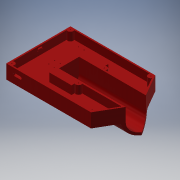
# Autodesk Inventor part: new base
Saved by Autodesk Inventor 2019 (Build 230136000, 136)
## iProperties
Created: 2019-03-15
Part Number: new base
Material: Generic
Document SubType Name: Modeling
Designer: Dell
Density: 1 g/cm^3
Appearance: Red
Mass: 2061.42 g
Surface Area: 3181.28 cm^2
Volume: 2061.42 cm^3
Author: Dell
Autodesk Inventor part; units mm, degrees
ref_plane "YZ Plane" through (0, 0, 0) normal (1, 0, 0) x (0, 1, 0)
ref_plane "XY Plane" through (0, 0, 0) normal (0, 0, 1) x (1, 0, 0)
sketch "Sketch2" plane through (0, 0, 0) normal (1, 0, 0) x (0, 1, 0)
  line L0 (50, 115) -> (0, 115)
  line L1 (0, 115) -> (0, 36)
  line L2 (0, 36) -> (50, 36)
  line L3 (50, 36) -> (50, 115)
  line L4 (50, -115) -> (0, -115)
  line L5 (0, -115) -> (0, -45)
  line L6 (0, -36) -> (50, -36)
  line L7 (50, -36) -> (50, -115)
  arc A0 (0, 45) -> (0, -45) centre (0, 0) ccw
  line L8 (0, 36) -> (0, -36)
  line L9 (0, 36) -> (0, -36)
  arc A1 (0, 36) -> (0, -36) centre (0, 0) ccw
  line L10 (0, -45) -> (0, -36)
  dimension "d7" = 50
  dimension "d8" = 79
  dimension "d12" = 90
  dimension "d14" = 50
  dimension "d16" = 72
  dimension "d117" = 79
  constraints: 23 end point, 5 point on circle, 5 point on line, 4 parallel, 3 collinear, 3 perpendicular, 2 centre point, 2 coincident, 2 horizontal, 1 midpoint, 1 vertical
  measures "d7" distance of L0.start L0.end
  measures "d8" distance of L2.end L0.start
  measures "d12" diameter of A0
  measures "d14" distance of L4.start L4.end
  measures "d16" diameter of A1
  measures "d117" distance of L4.end L6.start
extrude "Extrusion2" add sketch "Sketch2" along normal blind 370 contours L3 L2 L1 L0 | L1 A1 L10 A0 | L10 L6 L7 L4 L5
sketch "Sketch3" plane through (0, 50, -36) normal (0, 1, 0) x (1, 0, 0)
  line L0 (0, -72) -> (0, -151) projected
  line L1 (0, 0) -> (0, -72) projected
  line L2 (0, 79) -> (0, 0) projected
  line L3 (0, 79) -> (370, 79) projected
  line L4 (0, -151) -> (370, -151) projected
  line L5 (370, -72) -> (370, -151) projected
  line L6 (370, 0) -> (370, -72) projected
  line L7 (370, 79) -> (370, 0) projected
  line L8 (0, -151) -> (370, -151) projected
  line L9 (303.6047, -151) -> (370, -36)
  line L10 (370, -36) -> (303.6047, 79)
  line L11 (0, 79) -> (370, 79) projected
  line L12 (303.6047, -151) -> (370, -151)
  line L13 (370, -151) -> (370, 79)
  line L14 (370, 79) -> (303.6047, 79)
  line L15 (303.6047, -151) -> (303.6047, 79)
  point P0 (0, -36)
  dimension "d22" = 120
  dimension "d28" = 115
  constraints: 12 end point, 4 point on line, 1 horizontal, 1 midpoint, 1 parallel, 1 perpendicular, 1 vertical
  measures "d22" angle of L9 L10
  measures "d28" distance of L3.end L9.end
extrude "Extrusion3" cut sketch "Sketch3" against normal through all contours L9 L6 L5 L4 | L10 L3 L7 L6
sketch "Sketch4" plane through (0, 0, 0) normal (-1, 0, 0) x (0, 0, 1)
  arc A0 (-36, 0) -> (36, 0) centre (0, 0) ccw projected
  line L0 (36, 0) -> (36, 50) projected
  line L1 (-36, 50) -> (-36, 0) projected
  line L2 (36, 50) -> (-36, 50)
  constraints: 2 end point, 1 horizontal
extrude "Extrusion4" add sketch "Sketch4" against normal blind 110
sketch "Sketch5" plane through (0, 0, 0) normal (-1, 0, 0) x (0, 0, 1)
  arc A0 (-45, 0) -> (45, 0) centre (0, 0) ccw projected
  line L0 (45, 0) -> (-45, 0)
  constraints: 2 end point, 1 horizontal
extrude "Extrusion5" cut sketch "Sketch5" against normal blind 100
sketch "Sketch6" plane through (100, 0, 0) normal (-1, 0, 0) x (0, 0, 1)
  arc A0 (-45, 0) -> (45, 0) centre (0, 0) ccw projected
  arc A1 (-45, 0) -> (0, -45) centre (0, 0) ccw projected
  line L0 (45, 0) -> (115, 0) projected
  line L1 (-45, 0) -> (45, 0)
  constraints: 2 end point, 1 collinear
extrude "Extrusion6" add sketch "Sketch6" along normal blind 10
fillet "Fillet17" radius 10 1 edges at (90, 0, 0)
ref_plane "Work Plane1" through (0, -45, 0) normal (0, 1, 0) x (-1, 0, 0)
fillet "Fillet19" radius 10 4 edges at (85, 0, 45) (217.0096, 0, 45) (85, 0, -45) (217.0096, 0, -45)
sketch "Sketch26" plane through (0, -45, 0) normal (0, 1, 0) x (-1, 0, 0)
  circle A0 centre (-199.5, -1) radius 8
  line L0 (-199.5, -9) -> (-174.5, -9)
  line L1 (-174.5, -9) -> (-174.5, 7)
  line L2 (-174.5, 7) -> (-199.5, 7)
  line L3 (-199.5, 7) -> (-199.5, -9)
  point P0 (0, 0)
  dimension "d158" = 16
  dimension "d159" = 25
  constraints: 8 end point, 2 parallel, 1 horizontal, 1 midpoint, 1 perpendicular, 1 vertical alignment, 3 other
  measures "d158" distance of L0.end L1.end
  measures "d159" distance of L1.end L2.end
extrude "Extrusion15" cut sketch "Sketch26" along normal through all
sketch "Sketch31" plane through (0, 50, 115) normal (0, 1, 0) x (1, 0, 0)
  line L0 (303.6047, 0) -> (349.2154, 79) projected
  line L1 (110, 79) -> (349.2154, 79) projected
  line L2 (110, 151) -> (110, 79) projected
  line L3 (110, 151) -> (349.2154, 151) projected
  line L4 (349.2154, 151) -> (303.6047, 230) projected
  line L5 (0, 230) -> (303.6047, 230) projected
  line L6 (0, 230) -> (0, 0) projected
  line L7 (0, 0) -> (303.6047, 0) projected
  line L8 (300.718, 5) -> (340, 73.0385)
  line L9 (105, 181) -> (105, 49)
  line L10 (340, 156.9615) -> (300.718, 225)
  line L11 (5, 225) -> (300.718, 225)
  line L12 (5, 225) -> (5, 5)
  line L13 (5, 5) -> (300.718, 5)
  line L14 (105, 49) -> (185, 49)
  line L15 (185, 49) -> (185, 73.0385)
  line L16 (185, 73.0385) -> (340, 73.0385)
  line L17 (105, 181) -> (185, 181)
  line L18 (185, 181) -> (185, 156.9615)
  line L19 (185, 156.9615) -> (340, 156.9615)
  point P0 (0, 115)
  point P1 (1, 116)
  dimension "d183" = 5
  dimension "d184" = 5
  dimension "d185" = 5
  dimension "d186" = 5
  dimension "d188" = 5
  dimension "d189" = 5
  dimension "d190" = 155
  dimension "d191" = 80
  dimension "d192" = 30
  dimension "d193" = 30
  dimension "d194" = 155
  dimension "d195" = 80
  constraints: 24 end point, 4 horizontal, 2 perpendicular
  measures "d183" distance between parallel lines of L12 L6
  measures "d184" distance between parallel lines of L11 L5
  measures "d185" distance between parallel lines of L7 L13
  measures "d186" distance between parallel lines of L0 L8
  measures "d188" distance between parallel lines of L4 L10
  measures "d189" distance between parallel lines of L2 L9
  measures "d190" distance from line of L8.end L15
  measures "d191" distance between parallel lines of L15 L9
  measures "d192" distance between parallel lines of L14 L1
  measures "d193" distance between parallel lines of L17 L3
  measures "d194" distance from line of L10.start L18
  measures "d195" distance between parallel lines of L18 L9
extrude "Extrusion19" cut sketch "Sketch31" against normal blind 30 contours L13 L12 L11 L10 L19 L18 L17 L9 L14 L15 L16 L8
sketch "Sketch33" plane through (0, 50, 115) normal (0, 1, 0) x (1, 0, 0)
  line L0 (185, 73.0385) -> (340, 73.0385) projected
  line L1 (340, 73.0385) -> (300.718, 5) projected
  line L2 (300.718, 5) -> (5, 5) projected
  line L3 (5, 5) -> (5, 225) projected
  line L4 (5, 225) -> (300.718, 225) projected
  line L5 (300.718, 225) -> (340, 156.9615) projected
  line L6 (340, 156.9615) -> (185, 156.9615) projected
  line L7 (185, 156.9615) -> (185, 181) projected
  line L8 (185, 181) -> (105, 181) projected
  line L9 (105, 181) -> (105, 49) projected
  line L10 (105, 49) -> (185, 49) projected
  line L11 (185, 49) -> (185, 73.0385) projected
  line L12 (303.6047, 0) -> (349.2154, 79) projected
  line L13 (110, 79) -> (349.2154, 79) projected
  line L14 (110, 151) -> (110, 79) projected
  line L15 (110, 151) -> (349.2154, 151) projected
  line L16 (349.2154, 151) -> (303.6047, 230) projected
  line L17 (0, 230) -> (303.6047, 230) projected
  line L18 (0, 230) -> (0, 0) projected
  line L19 (0, 0) -> (303.6047, 0) projected
  circle A0 centre (10, 220) radius 10
  line L20 (0, 230) -> (303.6047, 230) projected
  line L21 (0, 230) -> (0, 0) projected
  circle A1 centre (10, 10) radius 10
  line L22 (0, 0) -> (303.6047, 0) projected
  circle A2 centre (297.8312, 10) radius 10
  circle A3 centre (297.8312, 220) radius 10
  line L23 (349.2154, 151) -> (303.6047, 230) projected
  circle A4 centre (190, 69) radius 10
  circle A5 centre (190, 161) radius 10
  line L24 (180, 54) -> (180, 79)
  line L25 (180, 153) -> (180, 178)
  line L26 (185, 73.0385) -> (340, 73.0385) projected
  line L27 (110, 79) -> (349.2154, 79) projected
  point P0 (0, 115)
  dimension "d200" = 20
  dimension "d201" = 20
  dimension "d202" = 20
  dimension "d203" = 20
  dimension "d204" = 20
  dimension "d205" = 20
  constraints: 12 tangent, 6 centre point, 4 end point, 2 vertical, 4 other
  measures "d200" diameter of A0
  measures "d201" diameter of A1
  measures "d202" diameter of A2
  measures "d203" diameter of A3
  measures "d204" diameter of A4
  measures "d205" diameter of A5
extrude "Extrusion21" add sketch "Sketch33" against normal through all contours L11 A4 L0 | L0 A4 L11 | A2 L2 L1 | L1 L2 A2 | A1 L3 L2 | L2 L3 A1 | A5 L7 L6 | A5 L6 L7 | A0 L4 L3 | L3 L4 A0 | A3 L5 L4 | A3 L4 L5
sketch "Sketch34" plane through (0, 50, 115) normal (0, 1, 0) x (1, 0, 0)
  line L0 (110, 151) -> (349.2154, 151) projected
  line L1 (349.2154, 151) -> (303.6047, 230) projected
  line L2 (0, 230) -> (303.6047, 230) projected
  line L3 (0, 230) -> (0, 0) projected
  line L4 (0, 0) -> (303.6047, 0) projected
  line L5 (303.6047, 0) -> (349.2154, 79) projected
  line L6 (110, 79) -> (349.2154, 79) projected
  line L7 (110, 151) -> (110, 79) projected
  line L8 (185, 169.6603) -> (185, 181) projected
  line L9 (185, 181) -> (105, 181) projected
  line L10 (105, 181) -> (105, 49) projected
  line L11 (105, 49) -> (185, 49) projected
  line L12 (185, 49) -> (185, 60.3397) projected
  arc A0 (185, 60.3397) -> (199.1483, 73.0385) centre (190, 69) ccw projected
  line L13 (199.1483, 73.0385) -> (340, 73.0385) projected
  line L14 (340, 73.0385) -> (306.4915, 15) projected
  arc A1 (306.4915, 15) -> (289.171, 5) centre (297.8312, 10) ccw projected
  line L15 (289.171, 5) -> (18.6603, 5) projected
  arc A2 (18.6603, 5) -> (5, 18.6603) centre (10, 10) ccw projected
  line L16 (5, 18.6603) -> (5, 211.3397) projected
  arc A3 (5, 211.3397) -> (18.6603, 225) centre (10, 220) ccw projected
  line L17 (18.6603, 225) -> (289.171, 225) projected
  arc A4 (289.171, 225) -> (306.4915, 215) centre (297.8312, 220) ccw projected
  line L18 (306.4915, 215) -> (340, 156.9615) projected
  line L19 (340, 156.9615) -> (199.1483, 156.9615) projected
  arc A5 (199.1483, 156.9615) -> (185, 169.6603) centre (190, 161) ccw projected
  circle A6 centre (10, 10) radius 2.5
  circle A7 centre (10, 220) radius 2.5
  circle A8 centre (190, 69) radius 2.5
  circle A9 centre (190, 161) radius 2.5
  circle A10 centre (297.8312, 220) radius 2.5
  circle A11 centre (297.8312, 10) radius 2.5
  point P0 (0, 115)
  dimension "d208" = 5
  dimension "d209" = 5
  dimension "d210" = 5
  dimension "d211" = 5
  dimension "d212" = 5
  dimension "d213" = 5
  constraints: 6 centre point, 6 coincident
  measures "d208" diameter of A6
  measures "d209" diameter of A7
  measures "d210" diameter of A8
  measures "d211" diameter of A9
  measures "d212" diameter of A10
  measures "d213" diameter of A11
hole "Hole9" at (190, 50, 46) at (190, 50, -46) at (297.8312, 50, -105) at (297.8312, 50, 105) at (10, 50, 105) at (10, 50, -105) direction (0, -1, 0) diameter 3 depth 10 tip angle 118
sketch "Sketch35" plane through (0, 0, -115) normal (0, -1, 0) x (1, 0, 0)
  circle A0 centre (10, 220) radius 1.5 projected
  circle A1 centre (297.8312, 220) radius 1.5 projected
  circle A2 centre (190, 161) radius 1.5 projected
  circle A3 centre (190, 69) radius 1.5 projected
  circle A4 centre (297.8312, 10) radius 1.5 projected
  circle A5 centre (10, 10) radius 1.5 projected
  point P0 (0, 115)
sketch "Sketch36" plane through (0, 0, -115) normal (0, -1, 0) x (1, 0, 0)
  point P0 (0, 115)
  point P1 (297.8416, 9.8606)
  point P2 (9.9012, 9.9983)
  point P3 (9.9435, 220.1266)
  point P4 (297.7535, 219.9704)
hole "Hole10" at (297.8416, 0, -105.1394) at (9.9012, 0, -105.0017) at (9.9435, 0, 105.1266) at (297.7535, 0, 104.9704) direction (0, 1, 0) diameter 3 depth 10 tip angle 118
sketch "Sketch37" plane through (0, 0, 0) normal (-1, 0, 0) x (0, 0, 1)
  line L0 (-115, 50) -> (115, 50) projected
  line L1 (-115, 0) -> (-115, 50) projected
  line L2 (115, 0) -> (-115, 0) projected
  line L3 (115, 50) -> (115, 0) projected
  line L4 (-7, 42.5) -> (4.5, 42.5) construction
  line L5 (-7, 40) -> (4.5, 40)
  line L6 (4.5, 45) -> (-7, 45)
  arc A0 (-7, 45) -> (-7, 40) centre (-7, 42.5) ccw
  arc A1 (4.5, 40) -> (4.5, 45) centre (4.5, 42.5) ccw
  line L7 (115, 50) -> (115, 0) projected
  line L8 (-115, 0) -> (-115, 50) projected
  line L9 (-115, 50) -> (115, 50) projected
  circle A2 centre (6.5, 36.744) radius 1.5
  circle A3 centre (-8.7, 36.744) radius 1.5
  point P0 (0, 0)
  point P1 (-1.25, 42.5)
  dimension "d228" = 5
  dimension "d229" = 108
  dimension "d230" = 108
  dimension "d231" = 5
  dimension "d232" = 11.5
  constraints: 8 end point, 4 centre point, 4 point on circle, 4 tangent, 1 horizontal, 1 midpoint, 1 parallel, 4 other
  measures "d228" diameter of A1
  measures "d229" distance edge to line of A1 L7
  measures "d230" distance from line of L8 L4.start
  measures "d231" distance between parallel lines of L6 L9
  measures "d232" distance of L5.start L5.end
extrude "Extrusion22" cut sketch "Sketch37" against normal up to surface (5 mm away) contours A0 L6 A1 L5 | A2 | A3
sketch "Sketch38" plane through (0, 0, -115) normal (0, -1, 0) x (1, 0, 0)
  ellipse E0 centre (48, 210.5298) end of major axis (45.5, 210.5298) minor radius 2.4999
  ellipse E1 centre (68, 210.5298) end of major axis (65.5, 210.5298) minor radius 2.4999
  ellipse E2 centre (48, 125.5334) end of major axis (45.5, 125.5334) minor radius 2.4999
  ellipse E3 centre (68, 125.5334) end of major axis (65.5, 125.5334) minor radius 2.4999
  ellipse E4 centre (48, 104.4472) end of major axis (45.5, 104.4472) minor radius 2.4998
  ellipse E5 centre (68, 104.4472) end of major axis (65.5, 104.4472) minor radius 2.4998
  ellipse E6 centre (48, 19.4553) end of major axis (45.5, 19.4553) minor radius 2.4998
  ellipse E7 centre (68, 19.4553) end of major axis (65.5, 19.4553) minor radius 2.4998
  point P0 (0, 115)
  constraints: 24 other
hole "Hole11" at (48, 0, 95.5298) at (68, 0, 95.5298) at (48, 0, 10.5334) at (68, 0, 10.5334) at (48, 0, -10.5528) at (68, 0, -10.5528) at (48, 0, -95.5447) at (68, 0, -95.5447) direction (0, 1, 0) diameter 5 depth 10 tip angle 118
sketch "Sketch39" plane through (0, 0, -115) normal (0, -1, 0) x (1, 0, 0)
  ellipse E0 centre (68, 210.5406) end of major axis (69.5, 210.5406) minor radius 1.4999
  ellipse E1 centre (48, 210.5406) end of major axis (49.5, 210.5406) minor radius 1.4999
  ellipse E2 centre (68, 125.5443) end of major axis (69.5, 125.5443) minor radius 1.4999
  ellipse E3 centre (48, 125.5443) end of major axis (49.5, 125.5443) minor radius 1.4999
  ellipse E4 centre (68, 104.4305) end of major axis (69.5, 104.4305) minor radius 1.4999
  circle A0 centre (48, 104.4472) radius 2.5 projected
  ellipse E5 centre (68, 19.4386) end of major axis (69.5, 19.4386) minor radius 1.4999
  ellipse E6 centre (48, 19.4386) end of major axis (49.5, 19.4386) minor radius 1.4999
  ellipse E7 centre (48, 104.4305) end of major axis (49.5, 104.4305) minor radius 1.4999
  point P0 (0, 115)
  constraints: 24 other
sketch "Sketch40" plane through (0, 20, 115) normal (0, 1, 0) x (1, 0, 0)
  point P0 (0, 115)
  point P1 (67.7179, 19.443)
  point P2 (47.9789, 19.2635)
  point P3 (67.8974, 104.4105)
  point P4 (47.9789, 104.5002)
  point P5 (67.7179, 125.7645)
  point P6 (47.9789, 125.4954)
  point P7 (67.8974, 210.8218)
  point P8 (48.0686, 210.732)
hole "Hole12" at (67.7179, 20, 95.557) at (47.9789, 20, 95.7365) at (67.8974, 20, 10.5895) at (47.9789, 20, 10.4998) at (67.7179, 20, -10.7645) at (47.9789, 20, -10.4954) at (67.8974, 20, -95.8218) at (48.0686, 20, -95.732) direction (0, -1, 0) diameter 3 depth 8 tip angle 118
sketch "Sketch41" plane through (289.171, 50, 110) normal (0, 0, -1) x (-1, 0, 0)
  line L0 (259.171, -20) -> (239.171, -20) construction
  line L1 (259.171, -15) -> (239.171, -15)
  line L2 (239.171, -25) -> (259.171, -25)
  arc A0 (259.171, -25) -> (259.171, -15) centre (259.171, -20) ccw
  arc A1 (239.171, -15) -> (239.171, -25) centre (239.171, -20) ccw
  line L3 (0, -30) -> (270.5107, -30) projected
  point P0 (289.171, -50)
  point P1 (249.171, -20)
  point P2 (284.171, 0)
  dimension "d249" = 10
  dimension "d250" = 20
  dimension "d251" = 5
  dimension "d252" = 35
  constraints: 8 end point, 4 point on circle, 4 tangent, 2 centre point, 1 horizontal, 1 midpoint, 1 parallel
  measures "d249" diameter of A1
  measures "d250" distance of L0.start L0.end
  measures "d251" distance between parallel lines of L2 L3
  measures "d252" horizontal distance of point (284.171, 0) point (249.171, -20)
extrude "Extrusion23" cut sketch "Sketch41" against normal through all
body "Solid2"
